Autodesk Fusion 360 part; units mm, degrees
(part 27 of 28)
  line L3756 (92.5423, 80.5012, -1.4859) -> (92.3675, 80.4122, -1.4859)
  line L3757 (92.3675, 80.4122, -1.4859) -> (92.181, 80.3516, -1.4859)
  line L3758 (92.181, 80.3516, -1.4859) -> (91.9873, 80.3209, -1.4859)
  line L3759 (91.9873, 80.3209, -1.4859) -> (91.8892, 80.317, -1.4859)
  line L3760 (91.8892, 80.317, -1.4859) -> (91.3892, 80.317, -1.4859)
  line L3761 (91.3892, 80.317, -1.4859) -> (91.2911, 80.3209, -1.4859)
  line L3762 (91.2911, 80.3209, -1.4859) -> (91.0974, 80.3516, -1.4859)
  line L3763 (91.0974, 80.3516, -1.4859) -> (90.9108, 80.4122, -1.4859)
  line L3764 (90.9108, 80.4122, -1.4859) -> (90.7361, 80.5012, -1.4859)
  line L3765 (90.7361, 80.5012, -1.4859) -> (90.5774, 80.6165, -1.4859)
  line L3766 (90.5774, 80.6165, -1.4859) -> (90.4387, 80.7552, -1.4859)
  line L3767 (90.4387, 80.7552, -1.4859) -> (90.3234, 80.9139, -1.4859)
  line L3768 (90.3234, 80.9139, -1.4859) -> (90.2343, 81.0887, -1.4859)
  line L3769 (90.2343, 81.0887, -1.4859) -> (90.1737, 81.2752, -1.4859)
  line L3770 (90.1737, 81.2752, -1.4859) -> (90.143, 81.469, -1.4859)
  line L3771 (90.143, 81.469, -1.4859) -> (90.143, 81.6651, -1.4859)
  line L3772 (90.143, 81.6651, -1.4859) -> (90.1737, 81.8588, -1.4859)
  line L3773 (90.1737, 81.8588, -1.4859) -> (90.2343, 82.0454, -1.4859)
  line L3774 (90.2343, 82.0454, -1.4859) -> (90.3234, 82.2202, -1.4859)
  line L3775 (90.3234, 82.2202, -1.4859) -> (90.4387, 82.3788, -1.4859)
  line L3776 (90.4387, 82.3788, -1.4859) -> (90.5774, 82.5175, -1.4859)
  line L3777 (90.5774, 82.5175, -1.4859) -> (90.7361, 82.6328, -1.4859)
  line L3778 (90.7361, 82.6328, -1.4859) -> (90.9108, 82.7219, -1.4859)
  line L3779 (90.9108, 82.7219, -1.4859) -> (91.0974, 82.7825, -1.4859)
  line L3780 (91.0974, 82.7825, -1.4859) -> (91.2911, 82.8132, -1.4859)
  line L3781 (91.2911, 82.8132, -1.4859) -> (91.3892, 82.817, -1.4859)
  line L3782 (91.3892, 82.817, -1.4859) -> (91.8892, 82.817, -1.4859)
  line L3783 (91.8892, 82.817, -1.4859) -> (91.9873, 82.8132, -1.4859)
  line L3784 (119.2923, 82.8132, -1.4859) -> (119.486, 82.7825, -1.4859)
  line L3785 (119.486, 82.7825, -1.4859) -> (119.6725, 82.7219, -1.4859)
  line L3786 (119.6725, 82.7219, -1.4859) -> (119.8473, 82.6328, -1.4859)
  line L3787 (119.8473, 82.6328, -1.4859) -> (120.006, 82.5175, -1.4859)
  line L3788 (120.006, 82.5175, -1.4859) -> (120.1447, 82.3788, -1.4859)
  line L3789 (120.1447, 82.3788, -1.4859) -> (120.26, 82.2202, -1.4859)
  line L3790 (120.26, 82.2202, -1.4859) -> (120.349, 82.0454, -1.4859)
  line L3791 (120.349, 82.0454, -1.4859) -> (120.4096, 81.8588, -1.4859)
  line L3792 (120.4096, 81.8588, -1.4859) -> (120.4403, 81.6651, -1.4859)
  line L3793 (120.4403, 81.6651, -1.4859) -> (120.4403, 81.469, -1.4859)
  line L3794 (120.4403, 81.469, -1.4859) -> (120.4096, 81.2752, -1.4859)
  line L3795 (120.4096, 81.2752, -1.4859) -> (120.349, 81.0887, -1.4859)
  line L3796 (120.349, 81.0887, -1.4859) -> (120.26, 80.9139, -1.4859)
  line L3797 (120.26, 80.9139, -1.4859) -> (120.1447, 80.7552, -1.4859)
  line L3798 (120.1447, 80.7552, -1.4859) -> (120.006, 80.6165, -1.4859)
  line L3799 (120.006, 80.6165, -1.4859) -> (119.8473, 80.5012, -1.4859)
  line L3800 (119.8473, 80.5012, -1.4859) -> (119.6725, 80.4122, -1.4859)
  line L3801 (119.6725, 80.4122, -1.4859) -> (119.486, 80.3516, -1.4859)
  line L3802 (119.486, 80.3516, -1.4859) -> (119.2923, 80.3209, -1.4859)
  line L3803 (119.2923, 80.3209, -1.4859) -> (119.1942, 80.317, -1.4859)
  line L3804 (119.1942, 80.317, -1.4859) -> (118.6942, 80.317, -1.4859)
  line L3805 (118.6942, 80.317, -1.4859) -> (118.5961, 80.3209, -1.4859)
  line L3806 (118.5961, 80.3209, -1.4859) -> (118.4024, 80.3516, -1.4859)
  line L3807 (118.4024, 80.3516, -1.4859) -> (118.2158, 80.4122, -1.4859)
  line L3808 (118.2158, 80.4122, -1.4859) -> (118.0411, 80.5012, -1.4859)
  line L3809 (118.0411, 80.5012, -1.4859) -> (117.8824, 80.6165, -1.4859)
  line L3810 (117.8824, 80.6165, -1.4859) -> (117.7437, 80.7552, -1.4859)
  line L3811 (117.7437, 80.7552, -1.4859) -> (117.6284, 80.9139, -1.4859)
  line L3812 (117.6284, 80.9139, -1.4859) -> (117.5393, 81.0887, -1.4859)
  line L3813 (117.5393, 81.0887, -1.4859) -> (117.4787, 81.2752, -1.4859)
  line L3814 (117.4787, 81.2752, -1.4859) -> (117.448, 81.469, -1.4859)
  line L3815 (117.448, 81.469, -1.4859) -> (117.448, 81.6651, -1.4859)
  line L3816 (117.448, 81.6651, -1.4859) -> (117.4787, 81.8588, -1.4859)
  line L3817 (117.4787, 81.8588, -1.4859) -> (117.5393, 82.0454, -1.4859)
  line L3818 (117.5393, 82.0454, -1.4859) -> (117.6284, 82.2202, -1.4859)
  line L3819 (117.6284, 82.2202, -1.4859) -> (117.7437, 82.3788, -1.4859)
  line L3820 (117.7437, 82.3788, -1.4859) -> (117.8824, 82.5175, -1.4859)
  line L3821 (117.8824, 82.5175, -1.4859) -> (118.0411, 82.6328, -1.4859)
  line L3822 (118.0411, 82.6328, -1.4859) -> (118.2158, 82.7219, -1.4859)
  line L3823 (118.2158, 82.7219, -1.4859) -> (118.4024, 82.7825, -1.4859)
  line L3824 (118.4024, 82.7825, -1.4859) -> (118.5961, 82.8132, -1.4859)
  line L3825 (118.5961, 82.8132, -1.4859) -> (118.6942, 82.817, -1.4859)
  line L3826 (118.6942, 82.817, -1.4859) -> (119.1942, 82.817, -1.4859)
  line L3827 (119.1942, 82.817, -1.4859) -> (119.2923, 82.8132, -1.4859)
  line L3828 (126.9123, 82.8132, -1.4859) -> (127.106, 82.7825, -1.4859)
  line L3829 (127.106, 82.7825, -1.4859) -> (127.2925, 82.7219, -1.4859)
  line L3830 (127.2925, 82.7219, -1.4859) -> (127.4673, 82.6328, -1.4859)
  line L3831 (127.4673, 82.6328, -1.4859) -> (127.626, 82.5175, -1.4859)
  line L3832 (127.626, 82.5175, -1.4859) -> (127.7647, 82.3788, -1.4859)
  line L3833 (127.7647, 82.3788, -1.4859) -> (127.88, 82.2202, -1.4859)
  line L3834 (127.88, 82.2202, -1.4859) -> (127.969, 82.0454, -1.4859)
  line L3835 (127.969, 82.0454, -1.4859) -> (128.0296, 81.8588, -1.4859)
  line L3836 (128.0296, 81.8588, -1.4859) -> (128.0603, 81.6651, -1.4859)
  line L3837 (128.0603, 81.6651, -1.4859) -> (128.0603, 81.469, -1.4859)
  line L3838 (128.0603, 81.469, -1.4859) -> (128.0296, 81.2752, -1.4859)
  line L3839 (128.0296, 81.2752, -1.4859) -> (127.969, 81.0887, -1.4859)
  line L3840 (127.969, 81.0887, -1.4859) -> (127.88, 80.9139, -1.4859)
  line L3841 (127.88, 80.9139, -1.4859) -> (127.7647, 80.7552, -1.4859)
  line L3842 (127.7647, 80.7552, -1.4859) -> (127.626, 80.6165, -1.4859)
  line L3843 (127.626, 80.6165, -1.4859) -> (127.4673, 80.5012, -1.4859)
  line L3844 (127.4673, 80.5012, -1.4859) -> (127.2925, 80.4122, -1.4859)
  line L3845 (127.2925, 80.4122, -1.4859) -> (127.106, 80.3516, -1.4859)
  line L3846 (127.106, 80.3516, -1.4859) -> (126.9123, 80.3209, -1.4859)
  line L3847 (126.9123, 80.3209, -1.4859) -> (126.8142, 80.317, -1.4859)
  line L3848 (126.8142, 80.317, -1.4859) -> (126.3142, 80.317, -1.4859)
  line L3849 (126.3142, 80.317, -1.4859) -> (126.2161, 80.3209, -1.4859)
  line L3850 (126.2161, 80.3209, -1.4859) -> (126.0224, 80.3516, -1.4859)
  line L3851 (126.0224, 80.3516, -1.4859) -> (125.8358, 80.4122, -1.4859)
  line L3852 (125.8358, 80.4122, -1.4859) -> (125.6611, 80.5012, -1.4859)
  line L3853 (125.6611, 80.5012, -1.4859) -> (125.5024, 80.6165, -1.4859)
  line L3854 (125.5024, 80.6165, -1.4859) -> (125.3637, 80.7552, -1.4859)
  line L3855 (125.3637, 80.7552, -1.4859) -> (125.2484, 80.9139, -1.4859)
  line L3856 (125.2484, 80.9139, -1.4859) -> (125.1593, 81.0887, -1.4859)
  line L3857 (125.1593, 81.0887, -1.4859) -> (125.0987, 81.2752, -1.4859)
  line L3858 (125.0987, 81.2752, -1.4859) -> (125.068, 81.469, -1.4859)
  line L3859 (125.068, 81.469, -1.4859) -> (125.068, 81.6651, -1.4859)
  line L3860 (125.068, 81.6651, -1.4859) -> (125.0987, 81.8588, -1.4859)
  line L3861 (125.0987, 81.8588, -1.4859) -> (125.1593, 82.0454, -1.4859)
  line L3862 (125.1593, 82.0454, -1.4859) -> (125.2484, 82.2202, -1.4859)
  line L3863 (125.2484, 82.2202, -1.4859) -> (125.3637, 82.3788, -1.4859)
  line L3864 (125.3637, 82.3788, -1.4859) -> (125.5024, 82.5175, -1.4859)
  line L3865 (125.5024, 82.5175, -1.4859) -> (125.6611, 82.6328, -1.4859)
  line L3866 (125.6611, 82.6328, -1.4859) -> (125.8358, 82.7219, -1.4859)
  line L3867 (125.8358, 82.7219, -1.4859) -> (126.0224, 82.7825, -1.4859)
  line L3868 (126.0224, 82.7825, -1.4859) -> (126.2161, 82.8132, -1.4859)
  line L3869 (126.2161, 82.8132, -1.4859) -> (126.3142, 82.817, -1.4859)
  line L3870 (126.3142, 82.817, -1.4859) -> (126.8142, 82.817, -1.4859)
  line L3871 (126.8142, 82.817, -1.4859) -> (126.9123, 82.8132, -1.4859)
  line L3872 (33.8845, 85.878, -1.4859) -> (34.071, 85.8174, -1.4859)
  line L3873 (34.071, 85.8174, -1.4859) -> (34.2458, 85.7283, -1.4859)
  line L3874 (34.2458, 85.7283, -1.4859) -> (34.4045, 85.613, -1.4859)
  line L3875 (34.4045, 85.613, -1.4859) -> (34.5432, 85.4743, -1.4859)
  line L3876 (34.5432, 85.4743, -1.4859) -> (34.6585, 85.3157, -1.4859)
  line L3877 (34.6585, 85.3157, -1.4859) -> (34.7475, 85.1409, -1.4859)
  line L3878 (34.7475, 85.1409, -1.4859) -> (34.8082, 84.9543, -1.4859)
  line L3879 (34.8082, 84.9543, -1.4859) -> (34.8388, 84.7606, -1.4859)
  line L3880 (34.8388, 84.7606, -1.4859) -> (34.8427, 84.6625, -1.4859)
  line L3881 (34.8427, 84.6625, -1.4859) -> (34.8427, 84.1625, -1.4859)
  line L3882 (34.8427, 84.1625, -1.4859) -> (34.8388, 84.0645, -1.4859)
  line L3883 (34.8388, 84.0645, -1.4859) -> (34.8082, 83.8707, -1.4859)
  line L3884 (34.8082, 83.8707, -1.4859) -> (34.7475, 83.6842, -1.4859)
  line L3885 (34.7475, 83.6842, -1.4859) -> (34.6585, 83.5094, -1.4859)
  line L3886 (34.6585, 83.5094, -1.4859) -> (34.5432, 83.3507, -1.4859)
  line L3887 (34.5432, 83.3507, -1.4859) -> (34.4045, 83.212, -1.4859)
  line L3888 (34.4045, 83.212, -1.4859) -> (34.2458, 83.0967, -1.4859)
  line L3889 (34.2458, 83.0967, -1.4859) -> (34.071, 83.0077, -1.4859)
  line L3890 (34.071, 83.0077, -1.4859) -> (33.8845, 82.9471, -1.4859)
  line L3891 (33.8845, 82.9471, -1.4859) -> (33.6908, 82.9164, -1.4859)
  line L3892 (33.6908, 82.9164, -1.4859) -> (33.4946, 82.9164, -1.4859)
  line L3893 (33.4946, 82.9164, -1.4859) -> (33.3009, 82.9471, -1.4859)
  line L3894 (33.3009, 82.9471, -1.4859) -> (33.1143, 83.0077, -1.4859)
  line L3895 (33.1143, 83.0077, -1.4859) -> (32.9396, 83.0967, -1.4859)
  line L3896 (32.9396, 83.0967, -1.4859) -> (32.7809, 83.212, -1.4859)
  line L3897 (32.7809, 83.212, -1.4859) -> (32.6422, 83.3507, -1.4859)
  line L3898 (32.6422, 83.3507, -1.4859) -> (32.5269, 83.5094, -1.4859)
  line L3899 (32.5269, 83.5094, -1.4859) -> (32.4378, 83.6842, -1.4859)
  line L3900 (32.4378, 83.6842, -1.4859) -> (32.3772, 83.8707, -1.4859)
  line L3901 (32.3772, 83.8707, -1.4859) -> (32.3465, 84.0645, -1.4859)
  line L3902 (32.3465, 84.0645, -1.4859) -> (32.3427, 84.1625, -1.4859)
  line L3903 (32.3427, 84.1625, -1.4859) -> (32.3427, 84.6625, -1.4859)
  line L3904 (32.3427, 84.6625, -1.4859) -> (32.3465, 84.7606, -1.4859)
  line L3905 (32.3465, 84.7606, -1.4859) -> (32.3772, 84.9543, -1.4859)
  line L3906 (32.3772, 84.9543, -1.4859) -> (32.4378, 85.1409, -1.4859)
  line L3907 (32.4378, 85.1409, -1.4859) -> (32.5269, 85.3157, -1.4859)
  line L3908 (32.5269, 85.3157, -1.4859) -> (32.6422, 85.4743, -1.4859)
  line L3909 (32.6422, 85.4743, -1.4859) -> (32.7809, 85.613, -1.4859)
  line L3910 (32.7809, 85.613, -1.4859) -> (32.9396, 85.7283, -1.4859)
  line L3911 (32.9396, 85.7283, -1.4859) -> (33.1143, 85.8174, -1.4859)
  line L3912 (33.1143, 85.8174, -1.4859) -> (33.3009, 85.878, -1.4859)
  line L3913 (33.3009, 85.878, -1.4859) -> (33.4946, 85.9087, -1.4859)
  line L3914 (33.4946, 85.9087, -1.4859) -> (33.6908, 85.9087, -1.4859)
  line L3915 (33.6908, 85.9087, -1.4859) -> (33.8845, 85.878, -1.4859)
  line L3916 (68.8095, 85.878, -1.4859) -> (68.996, 85.8174, -1.4859)
  line L3917 (68.996, 85.8174, -1.4859) -> (69.1708, 85.7283, -1.4859)
  line L3918 (69.1708, 85.7283, -1.4859) -> (69.3295, 85.613, -1.4859)
  line L3919 (69.3295, 85.613, -1.4859) -> (69.4682, 85.4743, -1.4859)
  line L3920 (69.4682, 85.4743, -1.4859) -> (69.5835, 85.3157, -1.4859)
  line L3921 (69.5835, 85.3157, -1.4859) -> (69.6725, 85.1409, -1.4859)
  line L3922 (69.6725, 85.1409, -1.4859) -> (69.7332, 84.9543, -1.4859)
  line L3923 (69.7332, 84.9543, -1.4859) -> (69.7638, 84.7606, -1.4859)
  line L3924 (69.7638, 84.7606, -1.4859) -> (69.7677, 84.6625, -1.4859)
  line L3925 (69.7677, 84.6625, -1.4859) -> (69.7677, 84.1625, -1.4859)
  line L3926 (69.7677, 84.1625, -1.4859) -> (69.7638, 84.0645, -1.4859)
  line L3927 (69.7638, 84.0645, -1.4859) -> (69.7332, 83.8707, -1.4859)
  line L3928 (69.7332, 83.8707, -1.4859) -> (69.6725, 83.6842, -1.4859)
  line L3929 (69.6725, 83.6842, -1.4859) -> (69.5835, 83.5094, -1.4859)
  line L3930 (69.5835, 83.5094, -1.4859) -> (69.4682, 83.3507, -1.4859)
  line L3931 (69.4682, 83.3507, -1.4859) -> (69.3295, 83.212, -1.4859)
  line L3932 (69.3295, 83.212, -1.4859) -> (69.1708, 83.0967, -1.4859)
  line L3933 (69.1708, 83.0967, -1.4859) -> (68.996, 83.0077, -1.4859)
  line L3934 (68.996, 83.0077, -1.4859) -> (68.8095, 82.9471, -1.4859)
  line L3935 (68.8095, 82.9471, -1.4859) -> (68.6158, 82.9164, -1.4859)
  line L3936 (68.6158, 82.9164, -1.4859) -> (68.4196, 82.9164, -1.4859)
  line L3937 (68.4196, 82.9164, -1.4859) -> (68.2259, 82.9471, -1.4859)
  line L3938 (68.2259, 82.9471, -1.4859) -> (68.0393, 83.0077, -1.4859)
  line L3939 (68.0393, 83.0077, -1.4859) -> (67.8646, 83.0967, -1.4859)
  line L3940 (67.8646, 83.0967, -1.4859) -> (67.7059, 83.212, -1.4859)
  line L3941 (67.7059, 83.212, -1.4859) -> (67.5672, 83.3507, -1.4859)
  line L3942 (67.5672, 83.3507, -1.4859) -> (67.4519, 83.5094, -1.4859)
  line L3943 (67.4519, 83.5094, -1.4859) -> (67.3628, 83.6842, -1.4859)
  line L3944 (67.3628, 83.6842, -1.4859) -> (67.3022, 83.8707, -1.4859)
  line L3945 (67.3022, 83.8707, -1.4859) -> (67.2715, 84.0645, -1.4859)
  line L3946 (67.2715, 84.0645, -1.4859) -> (67.2677, 84.1625, -1.4859)
  line L3947 (67.2677, 84.1625, -1.4859) -> (67.2677, 84.6625, -1.4859)
  line L3948 (67.2677, 84.6625, -1.4859) -> (67.2715, 84.7606, -1.4859)
  line L3949 (67.2715, 84.7606, -1.4859) -> (67.3022, 84.9543, -1.4859)
  line L3950 (67.3022, 84.9543, -1.4859) -> (67.3628, 85.1409, -1.4859)
  line L3951 (67.3628, 85.1409, -1.4859) -> (67.4519, 85.3157, -1.4859)
  line L3952 (67.4519, 85.3157, -1.4859) -> (67.5672, 85.4743, -1.4859)
  line L3953 (67.5672, 85.4743, -1.4859) -> (67.7059, 85.613, -1.4859)
  line L3954 (67.7059, 85.613, -1.4859) -> (67.8646, 85.7283, -1.4859)
  line L3955 (67.8646, 85.7283, -1.4859) -> (68.0393, 85.8174, -1.4859)
  line L3956 (68.0393, 85.8174, -1.4859) -> (68.2259, 85.878, -1.4859)
  line L3957 (68.2259, 85.878, -1.4859) -> (68.4196, 85.9087, -1.4859)
  line L3958 (68.4196, 85.9087, -1.4859) -> (68.6158, 85.9087, -1.4859)
  line L3959 (68.6158, 85.9087, -1.4859) -> (68.8095, 85.878, -1.4859)
  line L3960 (103.7345, 85.878, -1.4859) -> (103.921, 85.8174, -1.4859)
  line L3961 (103.921, 85.8174, -1.4859) -> (104.0958, 85.7283, -1.4859)
  line L3962 (104.0958, 85.7283, -1.4859) -> (104.2545, 85.613, -1.4859)
  line L3963 (104.2545, 85.613, -1.4859) -> (104.3932, 85.4743, -1.4859)
  line L3964 (104.3932, 85.4743, -1.4859) -> (104.5085, 85.3157, -1.4859)
  line L3965 (104.5085, 85.3157, -1.4859) -> (104.5975, 85.1409, -1.4859)
  line L3966 (104.5975, 85.1409, -1.4859) -> (104.6582, 84.9543, -1.4859)
  line L3967 (104.6582, 84.9543, -1.4859) -> (104.6888, 84.7606, -1.4859)
  line L3968 (104.6888, 84.7606, -1.4859) -> (104.6927, 84.6625, -1.4859)
  line L3969 (104.6927, 84.6625, -1.4859) -> (104.6927, 84.1625, -1.4859)
  line L3970 (104.6927, 84.1625, -1.4859) -> (104.6888, 84.0645, -1.4859)
  line L3971 (104.6888, 84.0645, -1.4859) -> (104.6582, 83.8707, -1.4859)
  line L3972 (104.6582, 83.8707, -1.4859) -> (104.5975, 83.6842, -1.4859)
  line L3973 (104.5975, 83.6842, -1.4859) -> (104.5085, 83.5094, -1.4859)
  line L3974 (104.5085, 83.5094, -1.4859) -> (104.3932, 83.3507, -1.4859)
  line L3975 (104.3932, 83.3507, -1.4859) -> (104.2545, 83.212, -1.4859)
  line L3976 (104.2545, 83.212, -1.4859) -> (104.0958, 83.0967, -1.4859)
  line L3977 (104.0958, 83.0967, -1.4859) -> (103.921, 83.0077, -1.4859)
  line L3978 (103.921, 83.0077, -1.4859) -> (103.7345, 82.9471, -1.4859)
  line L3979 (103.7345, 82.9471, -1.4859) -> (103.5408, 82.9164, -1.4859)
  line L3980 (103.5408, 82.9164, -1.4859) -> (103.3446, 82.9164, -1.4859)
  line L3981 (103.3446, 82.9164, -1.4859) -> (103.1509, 82.9471, -1.4859)
  line L3982 (103.1509, 82.9471, -1.4859) -> (102.9643, 83.0077, -1.4859)
  line L3983 (102.9643, 83.0077, -1.4859) -> (102.7896, 83.0967, -1.4859)
  line L3984 (102.7896, 83.0967, -1.4859) -> (102.6309, 83.212, -1.4859)
  line L3985 (102.6309, 83.212, -1.4859) -> (102.4922, 83.3507, -1.4859)
  line L3986 (102.4922, 83.3507, -1.4859) -> (102.3769, 83.5094, -1.4859)
  line L3987 (102.3769, 83.5094, -1.4859) -> (102.2878, 83.6842, -1.4859)
  line L3988 (102.2878, 83.6842, -1.4859) -> (102.2272, 83.8707, -1.4859)
  line L3989 (102.2272, 83.8707, -1.4859) -> (102.1965, 84.0645, -1.4859)
  line L3990 (102.1965, 84.0645, -1.4859) -> (102.1927, 84.1625, -1.4859)
  line L3991 (102.1927, 84.1625, -1.4859) -> (102.1927, 84.6625, -1.4859)
  line L3992 (102.1927, 84.6625, -1.4859) -> (102.1965, 84.7606, -1.4859)
  line L3993 (102.1965, 84.7606, -1.4859) -> (102.2272, 84.9543, -1.4859)
  line L3994 (102.2272, 84.9543, -1.4859) -> (102.2878, 85.1409, -1.4859)
  line L3995 (102.2878, 85.1409, -1.4859) -> (102.3769, 85.3157, -1.4859)
  line L3996 (102.3769, 85.3157, -1.4859) -> (102.4922, 85.4743, -1.4859)
  line L3997 (102.4922, 85.4743, -1.4859) -> (102.6309, 85.613, -1.4859)
  line L3998 (102.6309, 85.613, -1.4859) -> (102.7896, 85.7283, -1.4859)
  line L3999 (102.7896, 85.7283, -1.4859) -> (102.9643, 85.8174, -1.4859)
  line L4000 (102.9643, 85.8174, -1.4859) -> (103.1509, 85.878, -1.4859)
  line L4001 (103.1509, 85.878, -1.4859) -> (103.3446, 85.9087, -1.4859)
  line L4002 (103.3446, 85.9087, -1.4859) -> (103.5408, 85.9087, -1.4859)
  line L4003 (103.5408, 85.9087, -1.4859) -> (103.7345, 85.878, -1.4859)
  line L4004 (138.6595, 85.878, -1.4859) -> (138.846, 85.8174, -1.4859)
  line L4005 (138.846, 85.8174, -1.4859) -> (139.0208, 85.7283, -1.4859)
  line L4006 (139.0208, 85.7283, -1.4859) -> (139.1795, 85.613, -1.4859)
  line L4007 (139.1795, 85.613, -1.4859) -> (139.3182, 85.4743, -1.4859)
  line L4008 (139.3182, 85.4743, -1.4859) -> (139.4335, 85.3157, -1.4859)
  line L4009 (139.4335, 85.3157, -1.4859) -> (139.5225, 85.1409, -1.4859)
  line L4010 (139.5225, 85.1409, -1.4859) -> (139.5832, 84.9543, -1.4859)
  line L4011 (139.5832, 84.9543, -1.4859) -> (139.6138, 84.7606, -1.4859)
  line L4012 (139.6138, 84.7606, -1.4859) -> (139.6177, 84.6625, -1.4859)
  line L4013 (139.6177, 84.6625, -1.4859) -> (139.6177, 84.1625, -1.4859)
  line L4014 (139.6177, 84.1625, -1.4859) -> (139.6138, 84.0645, -1.4859)
  line L4015 (139.6138, 84.0645, -1.4859) -> (139.5832, 83.8707, -1.4859)
  line L4016 (139.5832, 83.8707, -1.4859) -> (139.5225, 83.6842, -1.4859)
  line L4017 (139.5225, 83.6842, -1.4859) -> (139.4335, 83.5094, -1.4859)
  line L4018 (139.4335, 83.5094, -1.4859) -> (139.3182, 83.3507, -1.4859)
  line L4019 (139.3182, 83.3507, -1.4859) -> (139.1795, 83.212, -1.4859)
  line L4020 (139.1795, 83.212, -1.4859) -> (139.0208, 83.0967, -1.4859)
  line L4021 (139.0208, 83.0967, -1.4859) -> (138.846, 83.0077, -1.4859)
  line L4022 (138.846, 83.0077, -1.4859) -> (138.6595, 82.9471, -1.4859)
  line L4023 (138.6595, 82.9471, -1.4859) -> (138.4658, 82.9164, -1.4859)
  line L4024 (138.4658, 82.9164, -1.4859) -> (138.2696, 82.9164, -1.4859)
  line L4025 (138.2696, 82.9164, -1.4859) -> (138.0759, 82.9471, -1.4859)
  line L4026 (138.0759, 82.9471, -1.4859) -> (137.8893, 83.0077, -1.4859)
  line L4027 (137.8893, 83.0077, -1.4859) -> (137.7146, 83.0967, -1.4859)
  line L4028 (137.7146, 83.0967, -1.4859) -> (137.5559, 83.212, -1.4859)
  line L4029 (137.5559, 83.212, -1.4859) -> (137.4172, 83.3507, -1.4859)
  line L4030 (137.4172, 83.3507, -1.4859) -> (137.3019, 83.5094, -1.4859)
  line L4031 (137.3019, 83.5094, -1.4859) -> (137.2128, 83.6842, -1.4859)
  line L4032 (137.2128, 83.6842, -1.4859) -> (137.1522, 83.8707, -1.4859)
  line L4033 (137.1522, 83.8707, -1.4859) -> (137.1215, 84.0645, -1.4859)
  line L4034 (137.1215, 84.0645, -1.4859) -> (137.1177, 84.1625, -1.4859)
  line L4035 (137.1177, 84.1625, -1.4859) -> (137.1177, 84.6625, -1.4859)
  line L4036 (137.1177, 84.6625, -1.4859) -> (137.1215, 84.7606, -1.4859)
  line L4037 (137.1215, 84.7606, -1.4859) -> (137.1522, 84.9543, -1.4859)
  line L4038 (137.1522, 84.9543, -1.4859) -> (137.2128, 85.1409, -1.4859)
  line L4039 (137.2128, 85.1409, -1.4859) -> (137.3019, 85.3157, -1.4859)
  line L4040 (137.3019, 85.3157, -1.4859) -> (137.4172, 85.4743, -1.4859)
  line L4041 (137.4172, 85.4743, -1.4859) -> (137.5559, 85.613, -1.4859)
  line L4042 (137.5559, 85.613, -1.4859) -> (137.7146, 85.7283, -1.4859)
  line L4043 (137.7146, 85.7283, -1.4859) -> (137.8893, 85.8174, -1.4859)
  line L4044 (137.8893, 85.8174, -1.4859) -> (138.0759, 85.878, -1.4859)
  line L4045 (138.0759, 85.878, -1.4859) -> (138.2696, 85.9087, -1.4859)
  line L4046 (138.2696, 85.9087, -1.4859) -> (138.4658, 85.9087, -1.4859)
  line L4047 (138.4658, 85.9087, -1.4859) -> (138.6595, 85.878, -1.4859)
  line L4048 (24.7774, 89.0483, -1.4859) -> (22.3274, 89.0483, -1.4859)
  line L4049 (22.3274, 89.0483, -1.4859) -> (22.3274, 92.0483, -1.4859)
  line L4050 (22.3274, 92.0483, -1.4859) -> (24.7774, 92.0483, -1.4859)
  line L4051 (24.7774, 92.0483, -1.4859) -> (24.7774, 89.0483, -1.4859)
  line L4052 (59.7024, 89.0483, -1.4859) -> (57.2524, 89.0483, -1.4859)
  line L4053 (57.2524, 89.0483, -1.4859) -> (57.2524, 92.0483, -1.4859)
  line L4054 (57.2524, 92.0483, -1.4859) -> (59.7024, 92.0483, -1.4859)
  line L4055 (59.7024, 92.0483, -1.4859) -> (59.7024, 89.0483, -1.4859)
  line L4056 (94.6274, 89.0483, -1.4859) -> (92.1774, 89.0483, -1.4859)
  line L4057 (92.1774, 89.0483, -1.4859) -> (92.1774, 92.0483, -1.4859)
  line L4058 (92.1774, 92.0483, -1.4859) -> (94.6274, 92.0483, -1.4859)
  line L4059 (94.6274, 92.0483, -1.4859) -> (94.6274, 89.0483, -1.4859)
  line L4060 (129.5524, 89.0483, -1.4859) -> (127.1024, 89.0483, -1.4859)
  line L4061 (127.1024, 89.0483, -1.4859) -> (127.1024, 92.0483, -1.4859)
  line L4062 (127.1024, 92.0483, -1.4859) -> (129.5524, 92.0483, -1.4859)
  line L4063 (129.5524, 92.0483, -1.4859) -> (129.5524, 89.0483, -1.4859)
  line L4064 (21.2983, 92.0145, -1.4859) -> (21.4812, 91.9551, -1.4859)
  line L4065 (21.4812, 91.9551, -1.4859) -> (21.6524, 91.8678, -1.4859)
  line L4066 (21.6524, 91.8678, -1.4859) -> (21.8079, 91.7548, -1.4859)
  line L4067 (21.8079, 91.7548, -1.4859) -> (21.9439, 91.6189, -1.4859)
  line L4068 (21.9439, 91.6189, -1.4859) -> (22.0569, 91.4634, -1.4859)
  line L4069 (22.0569, 91.4634, -1.4859) -> (22.1441, 91.2921, -1.4859)
  line L4070 (22.1441, 91.2921, -1.4859) -> (22.2035, 91.1093, -1.4859)
  line L4071 (22.2035, 91.1093, -1.4859) -> (22.2336, 90.9194, -1.4859)
  line L4072 (22.2336, 90.9194, -1.4859) -> (22.2374, 90.8233, -1.4859)
  line L4073 (22.2374, 90.8233, -1.4859) -> (22.2374, 90.2733, -1.4859)
  line L4074 (22.2374, 90.2733, -1.4859) -> (22.2336, 90.1772, -1.4859)
  line L4075 (22.2336, 90.1772, -1.4859) -> (22.2035, 89.9873, -1.4859)
  line L4076 (22.2035, 89.9873, -1.4859) -> (22.1441, 89.8045, -1.4859)
  line L4077 (22.1441, 89.8045, -1.4859) -> (22.0569, 89.6333, -1.4859)
  line L4078 (22.0569, 89.6333, -1.4859) -> (21.9439, 89.4777, -1.4859)
  line L4079 (21.9439, 89.4777, -1.4859) -> (21.8079, 89.3418, -1.4859)
  line L4080 (21.8079, 89.3418, -1.4859) -> (21.6524, 89.2288, -1.4859)
  line L4081 (21.6524, 89.2288, -1.4859) -> (21.4812, 89.1416, -1.4859)
  line L4082 (21.4812, 89.1416, -1.4859) -> (21.2983, 89.0822, -1.4859)
  line L4083 (21.2983, 89.0822, -1.4859) -> (21.1085, 89.0521, -1.4859)
  line L4084 (21.1085, 89.0521, -1.4859) -> (20.9163, 89.0521, -1.4859)
  line L4085 (20.9163, 89.0521, -1.4859) -> (20.7264, 89.0822, -1.4859)
  line L4086 (20.7264, 89.0822, -1.4859) -> (20.5436, 89.1416, -1.4859)
  line L4087 (20.5436, 89.1416, -1.4859) -> (20.3723, 89.2288, -1.4859)
  line L4088 (20.3723, 89.2288, -1.4859) -> (20.2168, 89.3418, -1.4859)
  line L4089 (20.2168, 89.3418, -1.4859) -> (20.0809, 89.4777, -1.4859)
  line L4090 (20.0809, 89.4777, -1.4859) -> (19.9679, 89.6333, -1.4859)
  line L4091 (19.9679, 89.6333, -1.4859) -> (19.8806, 89.8045, -1.4859)
  line L4092 (19.8806, 89.8045, -1.4859) -> (19.8212, 89.9873, -1.4859)
  line L4093 (19.8212, 89.9873, -1.4859) -> (19.7911, 90.1772, -1.4859)
  line L4094 (19.7911, 90.1772, -1.4859) -> (19.7874, 90.2733, -1.4859)
  line L4095 (19.7874, 90.2733, -1.4859) -> (19.7874, 90.8233, -1.4859)
  line L4096 (19.7874, 90.8233, -1.4859) -> (19.7911, 90.9194, -1.4859)
  line L4097 (19.7911, 90.9194, -1.4859) -> (19.8212, 91.1093, -1.4859)
  line L4098 (19.8212, 91.1093, -1.4859) -> (19.8806, 91.2921, -1.4859)
  line L4099 (19.8806, 91.2921, -1.4859) -> (19.9679, 91.4634, -1.4859)
  line L4100 (19.9679, 91.4634, -1.4859) -> (20.0809, 91.6189, -1.4859)
  line L4101 (20.0809, 91.6189, -1.4859) -> (20.2168, 91.7548, -1.4859)
  line L4102 (20.2168, 91.7548, -1.4859) -> (20.3723, 91.8678, -1.4859)
  line L4103 (20.3723, 91.8678, -1.4859) -> (20.5436, 91.9551, -1.4859)
  line L4104 (20.5436, 91.9551, -1.4859) -> (20.7264, 92.0145, -1.4859)
  line L4105 (20.7264, 92.0145, -1.4859) -> (20.9163, 92.0445, -1.4859)
  line L4106 (20.9163, 92.0445, -1.4859) -> (21.1085, 92.0445, -1.4859)
  line L4107 (21.1085, 92.0445, -1.4859) -> (21.2983, 92.0145, -1.4859)
  line L4108 (56.2233, 92.0145, -1.4859) -> (56.4062, 91.9551, -1.4859)
  line L4109 (56.4062, 91.9551, -1.4859) -> (56.5774, 91.8678, -1.4859)
  line L4110 (56.5774, 91.8678, -1.4859) -> (56.7329, 91.7548, -1.4859)
  line L4111 (56.7329, 91.7548, -1.4859) -> (56.8689, 91.6189, -1.4859)
  line L4112 (56.8689, 91.6189, -1.4859) -> (56.9819, 91.4634, -1.4859)
  line L4113 (56.9819, 91.4634, -1.4859) -> (57.0691, 91.2921, -1.4859)
  line L4114 (57.0691, 91.2921, -1.4859) -> (57.1285, 91.1093, -1.4859)
  line L4115 (57.1285, 91.1093, -1.4859) -> (57.1586, 90.9194, -1.4859)
  line L4116 (57.1586, 90.9194, -1.4859) -> (57.1624, 90.8233, -1.4859)
  line L4117 (57.1624, 90.8233, -1.4859) -> (57.1624, 90.2733, -1.4859)
  line L4118 (57.1624, 90.2733, -1.4859) -> (57.1586, 90.1772, -1.4859)
  line L4119 (57.1586, 90.1772, -1.4859) -> (57.1285, 89.9873, -1.4859)
  line L4120 (57.1285, 89.9873, -1.4859) -> (57.0691, 89.8045, -1.4859)
  line L4121 (57.0691, 89.8045, -1.4859) -> (56.9819, 89.6333, -1.4859)
  line L4122 (56.9819, 89.6333, -1.4859) -> (56.8689, 89.4777, -1.4859)
  line L4123 (56.8689, 89.4777, -1.4859) -> (56.7329, 89.3418, -1.4859)
  line L4124 (56.7329, 89.3418, -1.4859) -> (56.5774, 89.2288, -1.4859)
  line L4125 (56.5774, 89.2288, -1.4859) -> (56.4062, 89.1416, -1.4859)
  line L4126 (56.4062, 89.1416, -1.4859) -> (56.2233, 89.0822, -1.4859)
  line L4127 (56.2233, 89.0822, -1.4859) -> (56.0335, 89.0521, -1.4859)
  line L4128 (56.0335, 89.0521, -1.4859) -> (55.8413, 89.0521, -1.4859)
  line L4129 (55.8413, 89.0521, -1.4859) -> (55.6514, 89.0822, -1.4859)
  line L4130 (55.6514, 89.0822, -1.4859) -> (55.4686, 89.1416, -1.4859)
  line L4131 (55.4686, 89.1416, -1.4859) -> (55.2973, 89.2288, -1.4859)
  line L4132 (55.2973, 89.2288, -1.4859) -> (55.1418, 89.3418, -1.4859)
  line L4133 (55.1418, 89.3418, -1.4859) -> (55.0059, 89.4777, -1.4859)
  line L4134 (55.0059, 89.4777, -1.4859) -> (54.8929, 89.6333, -1.4859)
  line L4135 (54.8929, 89.6333, -1.4859) -> (54.8056, 89.8045, -1.4859)
  line L4136 (54.8056, 89.8045, -1.4859) -> (54.7462, 89.9873, -1.4859)
  line L4137 (54.7462, 89.9873, -1.4859) -> (54.7161, 90.1772, -1.4859)
  line L4138 (54.7161, 90.1772, -1.4859) -> (54.7124, 90.2733, -1.4859)
  line L4139 (54.7124, 90.2733, -1.4859) -> (54.7124, 90.8233, -1.4859)
  line L4140 (54.7124, 90.8233, -1.4859) -> (54.7161, 90.9194, -1.4859)
  line L4141 (54.7161, 90.9194, -1.4859) -> (54.7462, 91.1093, -1.4859)
  line L4142 (54.7462, 91.1093, -1.4859) -> (54.8056, 91.2921, -1.4859)
  line L4143 (54.8056, 91.2921, -1.4859) -> (54.8929, 91.4634, -1.4859)
  line L4144 (54.8929, 91.4634, -1.4859) -> (55.0059, 91.6189, -1.4859)
  line L4145 (55.0059, 91.6189, -1.4859) -> (55.1418, 91.7548, -1.4859)
  line L4146 (55.1418, 91.7548, -1.4859) -> (55.2973, 91.8678, -1.4859)
  line L4147 (55.2973, 91.8678, -1.4859) -> (55.4686, 91.9551, -1.4859)
  line L4148 (55.4686, 91.9551, -1.4859) -> (55.6514, 92.0145, -1.4859)
  line L4149 (55.6514, 92.0145, -1.4859) -> (55.8413, 92.0445, -1.4859)
  line L4150 (55.8413, 92.0445, -1.4859) -> (56.0335, 92.0445, -1.4859)
  line L4151 (56.0335, 92.0445, -1.4859) -> (56.2233, 92.0145, -1.4859)
  line L4152 (91.1483, 92.0145, -1.4859) -> (91.3312, 91.9551, -1.4859)
  line L4153 (91.3312, 91.9551, -1.4859) -> (91.5024, 91.8678, -1.4859)
  line L4154 (91.5024, 91.8678, -1.4859) -> (91.6579, 91.7548, -1.4859)
  line L4155 (91.6579, 91.7548, -1.4859) -> (91.7939, 91.6189, -1.4859)
  line L4156 (91.7939, 91.6189, -1.4859) -> (91.9069, 91.4634, -1.4859)
  line L4157 (91.9069, 91.4634, -1.4859) -> (91.9941, 91.2921, -1.4859)
  line L4158 (91.9941, 91.2921, -1.4859) -> (92.0535, 91.1093, -1.4859)
  line L4159 (92.0535, 91.1093, -1.4859) -> (92.0836, 90.9194, -1.4859)
  line L4160 (92.0836, 90.9194, -1.4859) -> (92.0874, 90.8233, -1.4859)
  line L4161 (92.0874, 90.8233, -1.4859) -> (92.0874, 90.2733, -1.4859)
  line L4162 (92.0874, 90.2733, -1.4859) -> (92.0836, 90.1772, -1.4859)
  line L4163 (92.0836, 90.1772, -1.4859) -> (92.0535, 89.9873, -1.4859)
  line L4164 (92.0535, 89.9873, -1.4859) -> (91.9941, 89.8045, -1.4859)
  line L4165 (91.9941, 89.8045, -1.4859) -> (91.9069, 89.6333, -1.4859)
  line L4166 (91.9069, 89.6333, -1.4859) -> (91.7939, 89.4777, -1.4859)
  line L4167 (91.7939, 89.4777, -1.4859) -> (91.6579, 89.3418, -1.4859)
  line L4168 (91.6579, 89.3418, -1.4859) -> (91.5024, 89.2288, -1.4859)
  line L4169 (91.5024, 89.2288, -1.4859) -> (91.3312, 89.1416, -1.4859)
  line L4170 (91.3312, 89.1416, -1.4859) -> (91.1483, 89.0822, -1.4859)
  line L4171 (91.1483, 89.0822, -1.4859) -> (90.9585, 89.0521, -1.4859)
  line L4172 (90.9585, 89.0521, -1.4859) -> (90.7663, 89.0521, -1.4859)
  line L4173 (90.7663, 89.0521, -1.4859) -> (90.5764, 89.0822, -1.4859)
  line L4174 (90.5764, 89.0822, -1.4859) -> (90.3936, 89.1416, -1.4859)
  line L4175 (90.3936, 89.1416, -1.4859) -> (90.2223, 89.2288, -1.4859)
  line L4176 (90.2223, 89.2288, -1.4859) -> (90.0668, 89.3418, -1.4859)
  line L4177 (90.0668, 89.3418, -1.4859) -> (89.9309, 89.4777, -1.4859)
  line L4178 (89.9309, 89.4777, -1.4859) -> (89.8179, 89.6333, -1.4859)
  line L4179 (89.8179, 89.6333, -1.4859) -> (89.7306, 89.8045, -1.4859)
  line L4180 (89.7306, 89.8045, -1.4859) -> (89.6712, 89.9873, -1.4859)
  line L4181 (89.6712, 89.9873, -1.4859) -> (89.6411, 90.1772, -1.4859)
  line L4182 (89.6411, 90.1772, -1.4859) -> (89.6374, 90.2733, -1.4859)
  line L4183 (89.6374, 90.2733, -1.4859) -> (89.6374, 90.8233, -1.4859)
  line L4184 (89.6374, 90.8233, -1.4859) -> (89.6411, 90.9194, -1.4859)
  line L4185 (89.6411, 90.9194, -1.4859) -> (89.6712, 91.1093, -1.4859)
  line L4186 (89.6712, 91.1093, -1.4859) -> (89.7306, 91.2921, -1.4859)
  line L4187 (89.7306, 91.2921, -1.4859) -> (89.8179, 91.4634, -1.4859)
  line L4188 (89.8179, 91.4634, -1.4859) -> (89.9309, 91.6189, -1.4859)
  line L4189 (89.9309, 91.6189, -1.4859) -> (90.0668, 91.7548, -1.4859)
  line L4190 (90.0668, 91.7548, -1.4859) -> (90.2223, 91.8678, -1.4859)
  line L4191 (90.2223, 91.8678, -1.4859) -> (90.3936, 91.9551, -1.4859)
  line L4192 (90.3936, 91.9551, -1.4859) -> (90.5764, 92.0145, -1.4859)
  line L4193 (90.5764, 92.0145, -1.4859) -> (90.7663, 92.0445, -1.4859)
  line L4194 (90.7663, 92.0445, -1.4859) -> (90.9585, 92.0445, -1.4859)
  line L4195 (90.9585, 92.0445, -1.4859) -> (91.1483, 92.0145, -1.4859)
  line L4196 (126.0733, 92.0145, -1.4859) -> (126.2562, 91.9551, -1.4859)
  line L4197 (126.2562, 91.9551, -1.4859) -> (126.4274, 91.8678, -1.4859)
  line L4198 (126.4274, 91.8678, -1.4859) -> (126.5829, 91.7548, -1.4859)
  line L4199 (126.5829, 91.7548, -1.4859) -> (126.7189, 91.6189, -1.4859)
  line L4200 (126.7189, 91.6189, -1.4859) -> (126.8319, 91.4634, -1.4859)
  line L4201 (126.8319, 91.4634, -1.4859) -> (126.9191, 91.2921, -1.4859)
  line L4202 (126.9191, 91.2921, -1.4859) -> (126.9785, 91.1093, -1.4859)
  line L4203 (126.9785, 91.1093, -1.4859) -> (127.0086, 90.9194, -1.4859)
  line L4204 (127.0086, 90.9194, -1.4859) -> (127.0124, 90.8233, -1.4859)
  line L4205 (127.0124, 90.8233, -1.4859) -> (127.0124, 90.2733, -1.4859)
  line L4206 (127.0124, 90.2733, -1.4859) -> (127.0086, 90.1772, -1.4859)
  line L4207 (127.0086, 90.1772, -1.4859) -> (126.9785, 89.9873, -1.4859)
  line L4208 (126.9785, 89.9873, -1.4859) -> (126.9191, 89.8045, -1.4859)
  line L4209 (126.9191, 89.8045, -1.4859) -> (126.8319, 89.6333, -1.4859)
  line L4210 (126.8319, 89.6333, -1.4859) -> (126.7189, 89.4777, -1.4859)
  line L4211 (126.7189, 89.4777, -1.4859) -> (126.5829, 89.3418, -1.4859)
  line L4212 (126.5829, 89.3418, -1.4859) -> (126.4274, 89.2288, -1.4859)
  line L4213 (126.4274, 89.2288, -1.4859) -> (126.2562, 89.1416, -1.4859)
  line L4214 (126.2562, 89.1416, -1.4859) -> (126.0733, 89.0822, -1.4859)
  line L4215 (126.0733, 89.0822, -1.4859) -> (125.8835, 89.0521, -1.4859)
  line L4216 (125.8835, 89.0521, -1.4859) -> (125.6913, 89.0521, -1.4859)
  line L4217 (125.6913, 89.0521, -1.4859) -> (125.5014, 89.0822, -1.4859)
  line L4218 (125.5014, 89.0822, -1.4859) -> (125.3186, 89.1416, -1.4859)
  line L4219 (125.3186, 89.1416, -1.4859) -> (125.1473, 89.2288, -1.4859)
  line L4220 (125.1473, 89.2288, -1.4859) -> (124.9918, 89.3418, -1.4859)
  line L4221 (124.9918, 89.3418, -1.4859) -> (124.8559, 89.4777, -1.4859)
  line L4222 (124.8559, 89.4777, -1.4859) -> (124.7429, 89.6333, -1.4859)
  line L4223 (124.7429, 89.6333, -1.4859) -> (124.6556, 89.8045, -1.4859)
  line L4224 (124.6556, 89.8045, -1.4859) -> (124.5962, 89.9873, -1.4859)
  line L4225 (124.5962, 89.9873, -1.4859) -> (124.5661, 90.1772, -1.4859)
  line L4226 (124.5661, 90.1772, -1.4859) -> (124.5624, 90.2733, -1.4859)
  line L4227 (124.5624, 90.2733, -1.4859) -> (124.5624, 90.8233, -1.4859)
  line L4228 (124.5624, 90.8233, -1.4859) -> (124.5661, 90.9194, -1.4859)
  line L4229 (124.5661, 90.9194, -1.4859) -> (124.5962, 91.1093, -1.4859)
  line L4230 (124.5962, 91.1093, -1.4859) -> (124.6556, 91.2921, -1.4859)
  line L4231 (124.6556, 91.2921, -1.4859) -> (124.7429, 91.4634, -1.4859)
  line L4232 (124.7429, 91.4634, -1.4859) -> (124.8559, 91.6189, -1.4859)
  line L4233 (124.8559, 91.6189, -1.4859) -> (124.9918, 91.7548, -1.4859)
  line L4234 (124.9918, 91.7548, -1.4859) -> (125.1473, 91.8678, -1.4859)
  line L4235 (125.1473, 91.8678, -1.4859) -> (125.3186, 91.9551, -1.4859)
  line L4236 (125.3186, 91.9551, -1.4859) -> (125.5014, 92.0145, -1.4859)
  line L4237 (125.5014, 92.0145, -1.4859) -> (125.6913, 92.0445, -1.4859)
  line L4238 (125.6913, 92.0445, -1.4859) -> (125.8835, 92.0445, -1.4859)
  line L4239 (125.8835, 92.0445, -1.4859) -> (126.0733, 92.0145, -1.4859)
  line L4240 (33.8845, 93.498, -1.4859) -> (34.071, 93.4374, -1.4859)
  line L4241 (34.071, 93.4374, -1.4859) -> (34.2458, 93.3483, -1.4859)
  line L4242 (34.2458, 93.3483, -1.4859) -> (34.4045, 93.233, -1.4859)
  line L4243 (34.4045, 93.233, -1.4859) -> (34.5432, 93.0943, -1.4859)
  line L4244 (34.5432, 93.0943, -1.4859) -> (34.6585, 92.9357, -1.4859)
  line L4245 (34.6585, 92.9357, -1.4859) -> (34.7475, 92.7609, -1.4859)
  line L4246 (34.7475, 92.7609, -1.4859) -> (34.8082, 92.5743, -1.4859)
  line L4247 (34.8082, 92.5743, -1.4859) -> (34.8388, 92.3806, -1.4859)
  line L4248 (34.8388, 92.3806, -1.4859) -> (34.8427, 92.2825, -1.4859)
  line L4249 (34.8427, 92.2825, -1.4859) -> (34.8427, 91.7825, -1.4859)
  line L4250 (34.8427, 91.7825, -1.4859) -> (34.8388, 91.6845, -1.4859)
  line L4251 (34.8388, 91.6845, -1.4859) -> (34.8082, 91.4907, -1.4859)
  line L4252 (34.8082, 91.4907, -1.4859) -> (34.7475, 91.3042, -1.4859)
  line L4253 (34.7475, 91.3042, -1.4859) -> (34.6585, 91.1294, -1.4859)
  line L4254 (34.6585, 91.1294, -1.4859) -> (34.5432, 90.9707, -1.4859)
  line L4255 (34.5432, 90.9707, -1.4859) -> (34.4045, 90.832, -1.4859)
  line L4256 (34.4045, 90.832, -1.4859) -> (34.2458, 90.7167, -1.4859)
  line L4257 (34.2458, 90.7167, -1.4859) -> (34.071, 90.6277, -1.4859)
  line L4258 (34.071, 90.6277, -1.4859) -> (33.8845, 90.5671, -1.4859)
  line L4259 (33.8845, 90.5671, -1.4859) -> (33.6908, 90.5364, -1.4859)
  line L4260 (33.6908, 90.5364, -1.4859) -> (33.4946, 90.5364, -1.4859)
  line L4261 (33.4946, 90.5364, -1.4859) -> (33.3009, 90.5671, -1.4859)
  line L4262 (33.3009, 90.5671, -1.4859) -> (33.1143, 90.6277, -1.4859)
  line L4263 (33.1143, 90.6277, -1.4859) -> (32.9396, 90.7167, -1.4859)
  line L4264 (32.9396, 90.7167, -1.4859) -> (32.7809, 90.832, -1.4859)
  line L4265 (32.7809, 90.832, -1.4859) -> (32.6422, 90.9707, -1.4859)
  line L4266 (32.6422, 90.9707, -1.4859) -> (32.5269, 91.1294, -1.4859)
  line L4267 (32.5269, 91.1294, -1.4859) -> (32.4378, 91.3042, -1.4859)
  line L4268 (32.4378, 91.3042, -1.4859) -> (32.3772, 91.4907, -1.4859)
  line L4269 (32.3772, 91.4907, -1.4859) -> (32.3465, 91.6845, -1.4859)
  line L4270 (32.3465, 91.6845, -1.4859) -> (32.3427, 91.7825, -1.4859)
  line L4271 (32.3427, 91.7825, -1.4859) -> (32.3427, 92.2825, -1.4859)
  line L4272 (32.3427, 92.2825, -1.4859) -> (32.3465, 92.3806, -1.4859)
  line L4273 (32.3465, 92.3806, -1.4859) -> (32.3772, 92.5743, -1.4859)
  line L4274 (32.3772, 92.5743, -1.4859) -> (32.4378, 92.7609, -1.4859)
  line L4275 (32.4378, 92.7609, -1.4859) -> (32.5269, 92.9357, -1.4859)
  line L4276 (32.5269, 92.9357, -1.4859) -> (32.6422, 93.0943, -1.4859)
  line L4277 (32.6422, 93.0943, -1.4859) -> (32.7809, 93.233, -1.4859)
  line L4278 (32.7809, 93.233, -1.4859) -> (32.9396, 93.3483, -1.4859)
  line L4279 (32.9396, 93.3483, -1.4859) -> (33.1143, 93.4374, -1.4859)
  line L4280 (33.1143, 93.4374, -1.4859) -> (33.3009, 93.498, -1.4859)
  line L4281 (33.3009, 93.498, -1.4859) -> (33.4946, 93.5287, -1.4859)
  line L4282 (33.4946, 93.5287, -1.4859) -> (33.6908, 93.5287, -1.4859)
  line L4283 (33.6908, 93.5287, -1.4859) -> (33.8845, 93.498, -1.4859)
  line L4284 (68.8095, 93.498, -1.4859) -> (68.996, 93.4374, -1.4859)
  line L4285 (68.996, 93.4374, -1.4859) -> (69.1708, 93.3483, -1.4859)
  line L4286 (69.1708, 93.3483, -1.4859) -> (69.3295, 93.233, -1.4859)
  line L4287 (69.3295, 93.233, -1.4859) -> (69.4682, 93.0943, -1.4859)
  line L4288 (69.4682, 93.0943, -1.4859) -> (69.5835, 92.9357, -1.4859)
  line L4289 (69.5835, 92.9357, -1.4859) -> (69.6725, 92.7609, -1.4859)
  line L4290 (69.6725, 92.7609, -1.4859) -> (69.7332, 92.5743, -1.4859)
  line L4291 (69.7332, 92.5743, -1.4859) -> (69.7638, 92.3806, -1.4859)
  line L4292 (69.7638, 92.3806, -1.4859) -> (69.7677, 92.2825, -1.4859)
  line L4293 (69.7677, 92.2825, -1.4859) -> (69.7677, 91.7825, -1.4859)
  line L4294 (69.7677, 91.7825, -1.4859) -> (69.7638, 91.6845, -1.4859)
  line L4295 (69.7638, 91.6845, -1.4859) -> (69.7332, 91.4907, -1.4859)
  line L4296 (69.7332, 91.4907, -1.4859) -> (69.6725, 91.3042, -1.4859)
  line L4297 (69.6725, 91.3042, -1.4859) -> (69.5835, 91.1294, -1.4859)
  line L4298 (69.5835, 91.1294, -1.4859) -> (69.4682, 90.9707, -1.4859)
  line L4299 (69.4682, 90.9707, -1.4859) -> (69.3295, 90.832, -1.4859)
  line L4300 (69.3295, 90.832, -1.4859) -> (69.1708, 90.7167, -1.4859)
  line L4301 (69.1708, 90.7167, -1.4859) -> (68.996, 90.6277, -1.4859)
  line L4302 (68.996, 90.6277, -1.4859) -> (68.8095, 90.5671, -1.4859)
  line L4303 (68.8095, 90.5671, -1.4859) -> (68.6158, 90.5364, -1.4859)
  line L4304 (68.6158, 90.5364, -1.4859) -> (68.4196, 90.5364, -1.4859)
  line L4305 (68.4196, 90.5364, -1.4859) -> (68.2259, 90.5671, -1.4859)
  line L4306 (68.2259, 90.5671, -1.4859) -> (68.0393, 90.6277, -1.4859)
  line L4307 (68.0393, 90.6277, -1.4859) -> (67.8646, 90.7167, -1.4859)
  line L4308 (67.8646, 90.7167, -1.4859) -> (67.7059, 90.832, -1.4859)
  line L4309 (67.7059, 90.832, -1.4859) -> (67.5672, 90.9707, -1.4859)
  line L4310 (67.5672, 90.9707, -1.4859) -> (67.4519, 91.1294, -1.4859)
  line L4311 (67.4519, 91.1294, -1.4859) -> (67.3628, 91.3042, -1.4859)
  line L4312 (67.3628, 91.3042, -1.4859) -> (67.3022, 91.4907, -1.4859)
  line L4313 (67.3022, 91.4907, -1.4859) -> (67.2715, 91.6845, -1.4859)
  line L4314 (67.2715, 91.6845, -1.4859) -> (67.2677, 91.7825, -1.4859)
  line L4315 (67.2677, 91.7825, -1.4859) -> (67.2677, 92.2825, -1.4859)
  line L4316 (67.2677, 92.2825, -1.4859) -> (67.2715, 92.3806, -1.4859)
  line L4317 (67.2715, 92.3806, -1.4859) -> (67.3022, 92.5743, -1.4859)
  line L4318 (67.3022, 92.5743, -1.4859) -> (67.3628, 92.7609, -1.4859)
  line L4319 (67.3628, 92.7609, -1.4859) -> (67.4519, 92.9357, -1.4859)
  line L4320 (67.4519, 92.9357, -1.4859) -> (67.5672, 93.0943, -1.4859)
  line L4321 (67.5672, 93.0943, -1.4859) -> (67.7059, 93.233, -1.4859)
  line L4322 (67.7059, 93.233, -1.4859) -> (67.8646, 93.3483, -1.4859)
  line L4323 (67.8646, 93.3483, -1.4859) -> (68.0393, 93.4374, -1.4859)
  line L4324 (68.0393, 93.4374, -1.4859) -> (68.2259, 93.498, -1.4859)
  line L4325 (68.2259, 93.498, -1.4859) -> (68.4196, 93.5287, -1.4859)
  line L4326 (68.4196, 93.5287, -1.4859) -> (68.6158, 93.5287, -1.4859)
  line L4327 (68.6158, 93.5287, -1.4859) -> (68.8095, 93.498, -1.4859)
  line L4328 (103.7345, 93.498, -1.4859) -> (103.921, 93.4374, -1.4859)
  line L4329 (103.921, 93.4374, -1.4859) -> (104.0958, 93.3483, -1.4859)
  line L4330 (104.0958, 93.3483, -1.4859) -> (104.2545, 93.233, -1.4859)
  line L4331 (104.2545, 93.233, -1.4859) -> (104.3932, 93.0943, -1.4859)
  line L4332 (104.3932, 93.0943, -1.4859) -> (104.5085, 92.9357, -1.4859)
  line L4333 (104.5085, 92.9357, -1.4859) -> (104.5975, 92.7609, -1.4859)
  line L4334 (104.5975, 92.7609, -1.4859) -> (104.6582, 92.5743, -1.4859)
  line L4335 (104.6582, 92.5743, -1.4859) -> (104.6888, 92.3806, -1.4859)
  line L4336 (104.6888, 92.3806, -1.4859) -> (104.6927, 92.2825, -1.4859)
  line L4337 (104.6927, 92.2825, -1.4859) -> (104.6927, 91.7825, -1.4859)
  line L4338 (104.6927, 91.7825, -1.4859) -> (104.6888, 91.6845, -1.4859)
  line L4339 (104.6888, 91.6845, -1.4859) -> (104.6582, 91.4907, -1.4859)
  line L4340 (104.6582, 91.4907, -1.4859) -> (104.5975, 91.3042, -1.4859)
  line L4341 (104.5975, 91.3042, -1.4859) -> (104.5085, 91.1294, -1.4859)
  line L4342 (104.5085, 91.1294, -1.4859) -> (104.3932, 90.9707, -1.4859)
  line L4343 (104.3932, 90.9707, -1.4859) -> (104.2545, 90.832, -1.4859)
  line L4344 (104.2545, 90.832, -1.4859) -> (104.0958, 90.7167, -1.4859)
  line L4345 (104.0958, 90.7167, -1.4859) -> (103.921, 90.6277, -1.4859)
  line L4346 (103.921, 90.6277, -1.4859) -> (103.7345, 90.5671, -1.4859)
  line L4347 (103.7345, 90.5671, -1.4859) -> (103.5408, 90.5364, -1.4859)
  line L4348 (103.5408, 90.5364, -1.4859) -> (103.3446, 90.5364, -1.4859)
  line L4349 (103.3446, 90.5364, -1.4859) -> (103.1509, 90.5671, -1.4859)
  line L4350 (103.1509, 90.5671, -1.4859) -> (102.9643, 90.6277, -1.4859)
  line L4351 (102.9643, 90.6277, -1.4859) -> (102.7896, 90.7167, -1.4859)
  line L4352 (102.7896, 90.7167, -1.4859) -> (102.6309, 90.832, -1.4859)
  line L4353 (102.6309, 90.832, -1.4859) -> (102.4922, 90.9707, -1.4859)
  line L4354 (102.4922, 90.9707, -1.4859) -> (102.3769, 91.1294, -1.4859)
  line L4355 (102.3769, 91.1294, -1.4859) -> (102.2878, 91.3042, -1.4859)
  line L4356 (102.2878, 91.3042, -1.4859) -> (102.2272, 91.4907, -1.4859)
  line L4357 (102.2272, 91.4907, -1.4859) -> (102.1965, 91.6845, -1.4859)
  line L4358 (102.1965, 91.6845, -1.4859) -> (102.1927, 91.7825, -1.4859)
  line L4359 (102.1927, 91.7825, -1.4859) -> (102.1927, 92.2825, -1.4859)
  line L4360 (102.1927, 92.2825, -1.4859) -> (102.1965, 92.3806, -1.4859)
  line L4361 (102.1965, 92.3806, -1.4859) -> (102.2272, 92.5743, -1.4859)
  line L4362 (102.2272, 92.5743, -1.4859) -> (102.2878, 92.7609, -1.4859)
  line L4363 (102.2878, 92.7609, -1.4859) -> (102.3769, 92.9357, -1.4859)
  line L4364 (102.3769, 92.9357, -1.4859) -> (102.4922, 93.0943, -1.4859)
  line L4365 (102.4922, 93.0943, -1.4859) -> (102.6309, 93.233, -1.4859)
  line L4366 (102.6309, 93.233, -1.4859) -> (102.7896, 93.3483, -1.4859)
  line L4367 (102.7896, 93.3483, -1.4859) -> (102.9643, 93.4374, -1.4859)
  line L4368 (102.9643, 93.4374, -1.4859) -> (103.1509, 93.498, -1.4859)
  line L4369 (103.1509, 93.498, -1.4859) -> (103.3446, 93.5287, -1.4859)
  line L4370 (103.3446, 93.5287, -1.4859) -> (103.5408, 93.5287, -1.4859)
  line L4371 (103.5408, 93.5287, -1.4859) -> (103.7345, 93.498, -1.4859)
  line L4372 (138.6595, 93.498, -1.4859) -> (138.846, 93.4374, -1.4859)
  line L4373 (138.846, 93.4374, -1.4859) -> (139.0208, 93.3483, -1.4859)
  line L4374 (139.0208, 93.3483, -1.4859) -> (139.1795, 93.233, -1.4859)
  line L4375 (139.1795, 93.233, -1.4859) -> (139.3182, 93.0943, -1.4859)
  line L4376 (139.3182, 93.0943, -1.4859) -> (139.4335, 92.9357, -1.4859)
  line L4377 (139.4335, 92.9357, -1.4859) -> (139.5225, 92.7609, -1.4859)
  line L4378 (139.5225, 92.7609, -1.4859) -> (139.5832, 92.5743, -1.4859)
  line L4379 (139.5832, 92.5743, -1.4859) -> (139.6138, 92.3806, -1.4859)
  line L4380 (139.6138, 92.3806, -1.4859) -> (139.6177, 92.2825, -1.4859)
  line L4381 (139.6177, 92.2825, -1.4859) -> (139.6177, 91.7825, -1.4859)
  line L4382 (139.6177, 91.7825, -1.4859) -> (139.6138, 91.6845, -1.4859)
  line L4383 (139.6138, 91.6845, -1.4859) -> (139.5832, 91.4907, -1.4859)
  line L4384 (139.5832, 91.4907, -1.4859) -> (139.5225, 91.3042, -1.4859)
  line L4385 (139.5225, 91.3042, -1.4859) -> (139.4335, 91.1294, -1.4859)
  line L4386 (139.4335, 91.1294, -1.4859) -> (139.3182, 90.9707, -1.4859)
  line L4387 (139.3182, 90.9707, -1.4859) -> (139.1795, 90.832, -1.4859)
  line L4388 (139.1795, 90.832, -1.4859) -> (139.0208, 90.7167, -1.4859)
  line L4389 (139.0208, 90.7167, -1.4859) -> (138.846, 90.6277, -1.4859)
  line L4390 (138.846, 90.6277, -1.4859) -> (138.6595, 90.5671, -1.4859)
  line L4391 (138.6595, 90.5671, -1.4859) -> (138.4658, 90.5364, -1.4859)
  line L4392 (138.4658, 90.5364, -1.4859) -> (138.2696, 90.5364, -1.4859)
  line L4393 (138.2696, 90.5364, -1.4859) -> (138.0759, 90.5671, -1.4859)
  line L4394 (138.0759, 90.5671, -1.4859) -> (137.8893, 90.6277, -1.4859)
  line L4395 (137.8893, 90.6277, -1.4859) -> (137.7146, 90.7167, -1.4859)
  line L4396 (137.7146, 90.7167, -1.4859) -> (137.5559, 90.832, -1.4859)
  line L4397 (137.5559, 90.832, -1.4859) -> (137.4172, 90.9707, -1.4859)
  line L4398 (137.4172, 90.9707, -1.4859) -> (137.3019, 91.1294, -1.4859)
  line L4399 (137.3019, 91.1294, -1.4859) -> (137.2128, 91.3042, -1.4859)
  line L4400 (137.2128, 91.3042, -1.4859) -> (137.1522, 91.4907, -1.4859)
  line L4401 (137.1522, 91.4907, -1.4859) -> (137.1215, 91.6845, -1.4859)
  line L4402 (137.1215, 91.6845, -1.4859) -> (137.1177, 91.7825, -1.4859)
  line L4403 (137.1177, 91.7825, -1.4859) -> (137.1177, 92.2825, -1.4859)
  line L4404 (137.1177, 92.2825, -1.4859) -> (137.1215, 92.3806, -1.4859)
  line L4405 (137.1215, 92.3806, -1.4859) -> (137.1522, 92.5743, -1.4859)
  line L4406 (137.1522, 92.5743, -1.4859) -> (137.2128, 92.7609, -1.4859)
  line L4407 (137.2128, 92.7609, -1.4859) -> (137.3019, 92.9357, -1.4859)
  line L4408 (137.3019, 92.9357, -1.4859) -> (137.4172, 93.0943, -1.4859)
  line L4409 (137.4172, 93.0943, -1.4859) -> (137.5559, 93.233, -1.4859)
  line L4410 (137.5559, 93.233, -1.4859) -> (137.7146, 93.3483, -1.4859)
  line L4411 (137.7146, 93.3483, -1.4859) -> (137.8893, 93.4374, -1.4859)
  line L4412 (137.8893, 93.4374, -1.4859) -> (138.0759, 93.498, -1.4859)
  line L4413 (138.0759, 93.498, -1.4859) -> (138.2696, 93.5287, -1.4859)
  line L4414 (138.2696, 93.5287, -1.4859) -> (138.4658, 93.5287, -1.4859)
  line L4415 (138.4658, 93.5287, -1.4859) -> (138.6595, 93.498, -1.4859)
  line L4416 (0.0231, 6.9946) -> (0.025, 6.985)
  line L4417 (0.025, 6.985) -> (0.025, 0.025)
  line L4418 (0.025, 0.025) -> (7.62, 0.025)
  line L4419 (7.62, 0.025) -> (7.6296, 0.0231)
  line L4420 (7.6296, 0.0231) -> (7.6431, 0.0096)
  line L4421 (7.6431, 0.0096) -> (7.6431, -0.0096)
  line L4422 (7.6431, -0.0096) -> (7.6296, -0.0231)
  line L4423 (7.6296, -0.0231) -> (7.62, -0.025)
  line L4424 (7.62, -0.025) -> (0.025, -0.025)
  line L4425 (0.025, -0.025) -> (0.025, -5.08)
  line L4426 (0.025, -5.08) -> (0.0231, -5.0896)
  line L4427 (0.0231, -5.0896) -> (0.0096, -5.1031)
  line L4428 (0.0096, -5.1031) -> (-0.0096, -5.1031)
  line L4429 (-0.0096, -5.1031) -> (-0.0231, -5.0896)
  line L4430 (-0.0231, -5.0896) -> (-0.025, -5.08)
  line L4431 (-0.025, -5.08) -> (-0.025, -0.025)
  line L4432 (-0.025, -0.025) -> (-5.08, -0.025)
  line L4433 (-5.08, -0.025) -> (-5.0896, -0.0231)
  line L4434 (-5.0896, -0.0231) -> (-5.1031, -0.0096)
  line L4435 (-5.1031, -0.0096) -> (-5.1031, 0.0096)
  line L4436 (-5.1031, 0.0096) -> (-5.0896, 0.0231)
  line L4437 (-5.0896, 0.0231) -> (-5.08, 0.025)
  line L4438 (-5.08, 0.025) -> (-0.025, 0.025)
  line L4439 (-0.025, 0.025) -> (-0.025, 6.985)
  line L4440 (-0.025, 6.985) -> (-0.0231, 6.9946)
  line L4441 (-0.0231, 6.9946) -> (-0.0096, 7.0081)
  line L4442 (-0.0096, 7.0081) -> (0.0096, 7.0081)
  line L4443 (0.0096, 7.0081) -> (0.0231, 6.9946)
  line L4444 (66.065, 36.83, -1.4859) -> (66.0746, 36.8281, -1.4859)
  line L4445 (66.0746, 36.8281, -1.4859) -> (66.0881, 36.8146, -1.4859)
  line L4446 (66.0881, 36.8146, -1.4859) -> (66.09, 36.805, -1.4859)
  line L4447 (66.09, 36.805, -1.4859) -> (66.09, 5.055, -1.4859)
  line L4448 (66.09, 5.055, -1.4859) -> (66.0881, 5.0454, -1.4859)
  line L4449 (66.0881, 5.0454, -1.4859) -> (66.0746, 5.0319, -1.4859)
  line L4450 (66.0746, 5.0319, -1.4859) -> (66.065, 5.03, -1.4859)
  line L4451 (66.065, 5.03, -1.4859) -> (8.28, 5.03, -1.4859)